Autodesk Fusion 360 part; units mm, degrees
(part 3 of 6)
sketch "OUTLINE - SOFFIT RAIL DOOR FEATURE 15" plane through (0, 0, 2346.24) normal (0, 0, 1) x (1, 0, 0) in component "611205 AIR - SOFFIT TOP RAIL - DOOR SIDE"
  line L0 (579.75, -641.14) -> (586.25, -641.14)
  line L1 (586.25, -641.14) -> (586.25, -635)
  line L2 (586.25, -635) -> (579.75, -635)
  line L3 (579.75, -635) -> (579.75, -641.14)
  dimension "d10633" = 6.5
  dimension "d10634" = 6.14
  dimension "d10635" = 579.75
  dimension "d10636" = 641.14
  constraint horizontal L0
  constraint vertical L1
  constraint horizontal L2
  constraint vertical L3
  measures "d10633" horizontal distance of L0.start L0.end
  measures "d10634" vertical distance of L0.start L2.end
  measures "d10635" horizontal distance of origin L0.start
  measures "d10636" vertical distance of origin L0.start
extrude "CUT - SOFFIT RAIL DOOR FEATURE 15" cut sketch "OUTLINE - SOFFIT RAIL DOOR FEATURE 15" along normal blind 3 bodies 19 in component "611205 AIR - SOFFIT TOP RAIL - DOOR SIDE"
ref_plane "WorkPlane5" through (0, 0, 2346.24) normal (0, 0, 1) x (1, 0, 0) in component "611205 AIR - SOFFIT TOP RAIL - DOOR SIDE"
sketch "HOLE - SOFFIT RAIL DOOR FEATURE 16" plane through (0, 0, 2346.24) normal (0, 0, 1) x (1, 0, 0) in component "611205 AIR - SOFFIT TOP RAIL - DOOR SIDE"
  circle A0 centre (583, -635) radius 3.25
  dimension "d10641" = 6.5
  dimension "d10642" = 583
  dimension "d10643" = 635
  measures "d10641" diameter of A0
  measures "d10642" horizontal distance of origin A0.centre
  measures "d10643" vertical distance of origin A0.centre
extrude "CUT - SOFFIT RAIL DOOR FEATURE 16" cut sketch "HOLE - SOFFIT RAIL DOOR FEATURE 16" along normal blind 3 bodies 19 in component "611205 AIR - SOFFIT TOP RAIL - DOOR SIDE"
ref_plane "WorkPlane4" through (0, 0, 2346.24) normal (0, 0, 1) x (1, 0, 0) in component "611209 AIR - SOFFIT TOP RAIL - ROOM SIDE"
sketch "OUTLINE - SOFFIT RAIL ROOM FEATURE 17" plane through (0, 0, 2346.24) normal (0, 0, 1) x (1, 0, 0) in component "611209 AIR - SOFFIT TOP RAIL - ROOM SIDE"
  line L0 (579.75, -309) -> (586.25, -309)
  line L1 (586.25, -309) -> (586.25, -291)
  line L2 (586.25, -291) -> (579.75, -291)
  line L3 (579.75, -291) -> (579.75, -309)
  dimension "d10648" = 6.5
  dimension "d10649" = 18
  dimension "d10650" = 579.75
  dimension "d10651" = 309
  constraint horizontal L0
  constraint vertical L1
  constraint horizontal L2
  constraint vertical L3
  measures "d10648" horizontal distance of L0.start L0.end
  measures "d10649" vertical distance of L0.start L2.end
  measures "d10650" horizontal distance of origin L0.start
  measures "d10651" vertical distance of origin L0.start
extrude "CUT - SOFFIT RAIL ROOM FEATURE 17" cut sketch "OUTLINE - SOFFIT RAIL ROOM FEATURE 17" along normal blind 3 bodies 20 in component "611209 AIR - SOFFIT TOP RAIL - ROOM SIDE"
ref_plane "WorkPlane5" through (0, 0, 2346.24) normal (0, 0, 1) x (1, 0, 0) in component "611209 AIR - SOFFIT TOP RAIL - ROOM SIDE"
sketch "HOLE - SOFFIT RAIL ROOM FEATURE 18" plane through (0, 0, 2346.24) normal (0, 0, 1) x (1, 0, 0) in component "611209 AIR - SOFFIT TOP RAIL - ROOM SIDE"
  circle A0 centre (583, -291) radius 3.25
  dimension "d10656" = 6.5
  dimension "d10657" = 583
  dimension "d10658" = 291
  measures "d10656" diameter of A0
  measures "d10657" horizontal distance of origin A0.centre
  measures "d10658" vertical distance of origin A0.centre
extrude "CUT - SOFFIT RAIL ROOM FEATURE 18" cut sketch "HOLE - SOFFIT RAIL ROOM FEATURE 18" along normal blind 3 bodies 20 in component "611209 AIR - SOFFIT TOP RAIL - ROOM SIDE"
ref_plane "WorkPlane6" through (0, 0, 2346.24) normal (0, 0, 1) x (1, 0, 0) in component "611209 AIR - SOFFIT TOP RAIL - ROOM SIDE"
sketch "HOLE - SOFFIT RAIL ROOM FEATURE 19" plane through (0, 0, 2346.24) normal (0, 0, 1) x (1, 0, 0) in component "611209 AIR - SOFFIT TOP RAIL - ROOM SIDE"
  circle A0 centre (-1100, -291) radius 3.5
  dimension "d10663" = 7
  dimension "d10664" = 1100
  dimension "d10665" = 291
  measures "d10663" diameter of A0
  measures "d10664" horizontal distance of origin A0.centre
  measures "d10665" vertical distance of origin A0.centre
extrude "CUT - SOFFIT RAIL ROOM FEATURE 19" cut sketch "HOLE - SOFFIT RAIL ROOM FEATURE 19" along normal blind 3 bodies 20 in component "611209 AIR - SOFFIT TOP RAIL - ROOM SIDE"
ref_plane "WorkPlane7" through (0, 0, 2346.24) normal (0, 0, 1) x (1, 0, 0) in component "611209 AIR - SOFFIT TOP RAIL - ROOM SIDE"
sketch "HOLE - SOFFIT RAIL ROOM FEATURE 20" plane through (0, 0, 2346.24) normal (0, 0, 1) x (1, 0, 0) in component "611209 AIR - SOFFIT TOP RAIL - ROOM SIDE"
  circle A0 centre (-950, -291) radius 3.5
  dimension "d10670" = 7
  dimension "d10671" = 950
  dimension "d10672" = 291
  measures "d10670" diameter of A0
  measures "d10671" horizontal distance of origin A0.centre
  measures "d10672" vertical distance of origin A0.centre
extrude "CUT - SOFFIT RAIL ROOM FEATURE 20" cut sketch "HOLE - SOFFIT RAIL ROOM FEATURE 20" along normal blind 3 bodies 20 in component "611209 AIR - SOFFIT TOP RAIL - ROOM SIDE"
ref_plane "WorkPlane4" through (0, -641.14, 0) normal (0, 1, 0) x (0, 0, 1) in component "611210 AIR - SOFFIT DOOR-SIDE PLATE"
sketch "HOLE - SOFFIT DOOR PLATE FEATURE 21" plane through (0, -641.14, 0) normal (0, 1, 0) x (1, 0, 0) in component "611210 AIR - SOFFIT DOOR-SIDE PLATE"
  circle A0 centre (499, -2140.1) radius 7
  dimension "d10677" = 14
  dimension "d10678" = 499
  dimension "d10679" = 2140.1
  measures "d10677" diameter of A0
  measures "d10678" horizontal distance of origin A0.centre
  measures "d10679" vertical distance of origin A0.centre
extrude "CUT - SOFFIT DOOR PLATE FEATURE 21" cut sketch "HOLE - SOFFIT DOOR PLATE FEATURE 21" along normal blind 2 bodies 21 in component "611210 AIR - SOFFIT DOOR-SIDE PLATE"
ref_plane "WorkPlane5" through (0, -641.14, 0) normal (0, 1, 0) x (0, 0, 1) in component "611210 AIR - SOFFIT DOOR-SIDE PLATE"
sketch "HOLE - SOFFIT DOOR PLATE FEATURE 22" plane through (0, -641.14, 0) normal (0, 1, 0) x (1, 0, 0) in component "611210 AIR - SOFFIT DOOR-SIDE PLATE"
  circle A0 centre (821.7, -2140.1) radius 7
  dimension "d10684" = 14
  dimension "d10685" = 821.7
  dimension "d10686" = 2140.1
  measures "d10684" diameter of A0
  measures "d10685" horizontal distance of origin A0.centre
  measures "d10686" vertical distance of origin A0.centre
extrude "CUT - SOFFIT DOOR PLATE FEATURE 22" cut sketch "HOLE - SOFFIT DOOR PLATE FEATURE 22" along normal blind 2 bodies 21 in component "611210 AIR - SOFFIT DOOR-SIDE PLATE"
ref_plane "WorkPlane6" through (0, -641.14, 0) normal (0, 1, 0) x (0, 0, 1) in component "611210 AIR - SOFFIT DOOR-SIDE PLATE"
sketch "HOLE - SOFFIT DOOR PLATE FEATURE 23" plane through (0, -641.14, 0) normal (0, 1, 0) x (1, 0, 0) in component "611210 AIR - SOFFIT DOOR-SIDE PLATE"
  circle A0 centre (1144.4, -2140.1) radius 7
  dimension "d10691" = 14
  dimension "d10692" = 1144.4
  dimension "d10693" = 2140.1
  measures "d10691" diameter of A0
  measures "d10692" horizontal distance of origin A0.centre
  measures "d10693" vertical distance of origin A0.centre
extrude "CUT - SOFFIT DOOR PLATE FEATURE 23" cut sketch "HOLE - SOFFIT DOOR PLATE FEATURE 23" along normal blind 2 bodies 21 in component "611210 AIR - SOFFIT DOOR-SIDE PLATE"
ref_plane "WorkPlane2" through (0, 0, 1698) normal (0, 0, 1) x (1, 0, 0) in component "611404 AIR - FAN BOX BULKHEAD - SUPPLY"
sketch "HOLE - FAN BOX BULKHEAD SUPPLY FEATURE 24" plane through (0, 0, 1698) normal (0, 0, 1) x (1, 0, 0) in component "611404 AIR - FAN BOX BULKHEAD - SUPPLY"
  circle A0 centre (756.5, -741.5) radius 67.5
  dimension "d10698" = 135
  dimension "d10699" = 756.5
  dimension "d10700" = 741.5
  measures "d10698" diameter of A0
  measures "d10699" horizontal distance of origin A0.centre
  measures "d10700" vertical distance of origin A0.centre
extrude "CUT - FAN BOX BULKHEAD SUPPLY FEATURE 24" cut sketch "HOLE - FAN BOX BULKHEAD SUPPLY FEATURE 24" along normal blind 2 bodies 38 in component "611404 AIR - FAN BOX BULKHEAD - SUPPLY"
ref_plane "WorkPlane3" through (0, 0, 1698) normal (0, 0, 1) x (1, 0, 0) in component "611404 AIR - FAN BOX BULKHEAD - SUPPLY"
sketch "HOLE - FAN BOX BULKHEAD SUPPLY FEATURE 25" plane through (0, 0, 1698) normal (0, 0, 1) x (1, 0, 0) in component "611404 AIR - FAN BOX BULKHEAD - SUPPLY"
  circle A0 centre (694.25, -803.75) radius 2.25
  dimension "d10705" = 4.5
  dimension "d10706" = 694.25
  dimension "d10707" = 803.75
  measures "d10705" diameter of A0
  measures "d10706" horizontal distance of origin A0.centre
  measures "d10707" vertical distance of origin A0.centre
extrude "CUT - FAN BOX BULKHEAD SUPPLY FEATURE 25" cut sketch "HOLE - FAN BOX BULKHEAD SUPPLY FEATURE 25" along normal blind 2 bodies 38 in component "611404 AIR - FAN BOX BULKHEAD - SUPPLY"
ref_plane "WorkPlane4" through (0, 0, 1698) normal (0, 0, 1) x (1, 0, 0) in component "611404 AIR - FAN BOX BULKHEAD - SUPPLY"
sketch "HOLE - FAN BOX BULKHEAD SUPPLY FEATURE 26" plane through (0, 0, 1698) normal (0, 0, 1) x (1, 0, 0) in component "611404 AIR - FAN BOX BULKHEAD - SUPPLY"
  circle A0 centre (694.25, -679.25) radius 2.25
  dimension "d10712" = 4.5
  dimension "d10713" = 694.25
  dimension "d10714" = 679.25
  measures "d10712" diameter of A0
  measures "d10713" horizontal distance of origin A0.centre
  measures "d10714" vertical distance of origin A0.centre
extrude "CUT - FAN BOX BULKHEAD SUPPLY FEATURE 26" cut sketch "HOLE - FAN BOX BULKHEAD SUPPLY FEATURE 26" along normal blind 2 bodies 38 in component "611404 AIR - FAN BOX BULKHEAD - SUPPLY"
ref_plane "WorkPlane5" through (0, 0, 1698) normal (0, 0, 1) x (1, 0, 0) in component "611404 AIR - FAN BOX BULKHEAD - SUPPLY"
sketch "HOLE - FAN BOX BULKHEAD SUPPLY FEATURE 27" plane through (0, 0, 1698) normal (0, 0, 1) x (1, 0, 0) in component "611404 AIR - FAN BOX BULKHEAD - SUPPLY"
  circle A0 centre (818.75, -803.75) radius 2.25
  dimension "d10719" = 4.5
  dimension "d10720" = 818.75
  dimension "d10721" = 803.75
  measures "d10719" diameter of A0
  measures "d10720" horizontal distance of origin A0.centre
  measures "d10721" vertical distance of origin A0.centre
extrude "CUT - FAN BOX BULKHEAD SUPPLY FEATURE 27" cut sketch "HOLE - FAN BOX BULKHEAD SUPPLY FEATURE 27" along normal blind 2 bodies 38 in component "611404 AIR - FAN BOX BULKHEAD - SUPPLY"
ref_plane "WorkPlane6" through (0, 0, 1698) normal (0, 0, 1) x (1, 0, 0) in component "611404 AIR - FAN BOX BULKHEAD - SUPPLY"
sketch "HOLE - FAN BOX BULKHEAD SUPPLY FEATURE 28" plane through (0, 0, 1698) normal (0, 0, 1) x (1, 0, 0) in component "611404 AIR - FAN BOX BULKHEAD - SUPPLY"
  circle A0 centre (818.75, -679.25) radius 2.25
  dimension "d10726" = 4.5
  dimension "d10727" = 818.75
  dimension "d10728" = 679.25
  measures "d10726" diameter of A0
  measures "d10727" horizontal distance of origin A0.centre
  measures "d10728" vertical distance of origin A0.centre
extrude "CUT - FAN BOX BULKHEAD SUPPLY FEATURE 28" cut sketch "HOLE - FAN BOX BULKHEAD SUPPLY FEATURE 28" along normal blind 2 bodies 38 in component "611404 AIR - FAN BOX BULKHEAD - SUPPLY"
ref_plane "WorkPlane7" through (0, 0, 1698) normal (0, 0, 1) x (1, 0, 0) in component "611404 AIR - FAN BOX BULKHEAD - SUPPLY"
sketch "HOLE - FAN BOX BULKHEAD SUPPLY FEATURE 29" plane through (0, 0, 1698) normal (0, 0, 1) x (1, 0, 0) in component "611404 AIR - FAN BOX BULKHEAD - SUPPLY"
  circle A0 centre (903.5, -741.5) radius 67.5
  dimension "d10733" = 135
  dimension "d10734" = 903.5
  dimension "d10735" = 741.5
  measures "d10733" diameter of A0
  measures "d10734" horizontal distance of origin A0.centre
  measures "d10735" vertical distance of origin A0.centre
extrude "CUT - FAN BOX BULKHEAD SUPPLY FEATURE 29" cut sketch "HOLE - FAN BOX BULKHEAD SUPPLY FEATURE 29" along normal blind 2 bodies 38 in component "611404 AIR - FAN BOX BULKHEAD - SUPPLY"
ref_plane "WorkPlane8" through (0, 0, 1698) normal (0, 0, 1) x (1, 0, 0) in component "611404 AIR - FAN BOX BULKHEAD - SUPPLY"
sketch "HOLE - FAN BOX BULKHEAD SUPPLY FEATURE 30" plane through (0, 0, 1698) normal (0, 0, 1) x (1, 0, 0) in component "611404 AIR - FAN BOX BULKHEAD - SUPPLY"
  circle A0 centre (841.25, -803.75) radius 2.25
  dimension "d10740" = 4.5
  dimension "d10741" = 841.25
  dimension "d10742" = 803.75
  measures "d10740" diameter of A0
  measures "d10741" horizontal distance of origin A0.centre
  measures "d10742" vertical distance of origin A0.centre
extrude "CUT - FAN BOX BULKHEAD SUPPLY FEATURE 30" cut sketch "HOLE - FAN BOX BULKHEAD SUPPLY FEATURE 30" along normal blind 2 bodies 38 in component "611404 AIR - FAN BOX BULKHEAD - SUPPLY"
ref_plane "WorkPlane9" through (0, 0, 1698) normal (0, 0, 1) x (1, 0, 0) in component "611404 AIR - FAN BOX BULKHEAD - SUPPLY"
sketch "HOLE - FAN BOX BULKHEAD SUPPLY FEATURE 31" plane through (0, 0, 1698) normal (0, 0, 1) x (1, 0, 0) in component "611404 AIR - FAN BOX BULKHEAD - SUPPLY"
  circle A0 centre (841.25, -679.25) radius 2.25
  dimension "d10747" = 4.5
  dimension "d10748" = 841.25
  dimension "d10749" = 679.25
  measures "d10747" diameter of A0
  measures "d10748" horizontal distance of origin A0.centre
  measures "d10749" vertical distance of origin A0.centre
extrude "CUT - FAN BOX BULKHEAD SUPPLY FEATURE 31" cut sketch "HOLE - FAN BOX BULKHEAD SUPPLY FEATURE 31" along normal blind 2 bodies 38 in component "611404 AIR - FAN BOX BULKHEAD - SUPPLY"
ref_plane "WorkPlane10" through (0, 0, 1698) normal (0, 0, 1) x (1, 0, 0) in component "611404 AIR - FAN BOX BULKHEAD - SUPPLY"
sketch "HOLE - FAN BOX BULKHEAD SUPPLY FEATURE 32" plane through (0, 0, 1698) normal (0, 0, 1) x (1, 0, 0) in component "611404 AIR - FAN BOX BULKHEAD - SUPPLY"
  circle A0 centre (965.75, -803.75) radius 2.25
  dimension "d10754" = 4.5
  dimension "d10755" = 965.75
  dimension "d10756" = 803.75
  measures "d10754" diameter of A0
  measures "d10755" horizontal distance of origin A0.centre
  measures "d10756" vertical distance of origin A0.centre
extrude "CUT - FAN BOX BULKHEAD SUPPLY FEATURE 32" cut sketch "HOLE - FAN BOX BULKHEAD SUPPLY FEATURE 32" along normal blind 2 bodies 38 in component "611404 AIR - FAN BOX BULKHEAD - SUPPLY"
ref_plane "WorkPlane11" through (0, 0, 1698) normal (0, 0, 1) x (1, 0, 0) in component "611404 AIR - FAN BOX BULKHEAD - SUPPLY"
sketch "HOLE - FAN BOX BULKHEAD SUPPLY FEATURE 33" plane through (0, 0, 1698) normal (0, 0, 1) x (1, 0, 0) in component "611404 AIR - FAN BOX BULKHEAD - SUPPLY"
  circle A0 centre (965.75, -679.25) radius 2.25
  dimension "d10761" = 4.5
  dimension "d10762" = 965.75
  dimension "d10763" = 679.25
  measures "d10761" diameter of A0
  measures "d10762" horizontal distance of origin A0.centre
  measures "d10763" vertical distance of origin A0.centre
extrude "CUT - FAN BOX BULKHEAD SUPPLY FEATURE 33" cut sketch "HOLE - FAN BOX BULKHEAD SUPPLY FEATURE 33" along normal blind 2 bodies 38 in component "611404 AIR - FAN BOX BULKHEAD - SUPPLY"
ref_plane "WorkPlane2" through (0, 0, 2330) normal (0, 0, 1) x (1, 0, 0) in component "611403 AIR - FAN BOX BULKHEAD - EXHAUST"
sketch "HOLE - FAN BOX BULKHEAD EXHAUST FEATURE 34" plane through (0, 0, 2330) normal (0, 0, 1) x (1, 0, 0) in component "611403 AIR - FAN BOX BULKHEAD - EXHAUST"
  circle A0 centre (939.75, -479.14) radius 67.5
  dimension "d10768" = 135
  dimension "d10769" = 939.75
  dimension "d10770" = 479.14
  measures "d10768" diameter of A0
  measures "d10769" horizontal distance of origin A0.centre
  measures "d10770" vertical distance of origin A0.centre
extrude "CUT - FAN BOX BULKHEAD EXHAUST FEATURE 34" cut sketch "HOLE - FAN BOX BULKHEAD EXHAUST FEATURE 34" along normal blind 2 bodies 33 in component "611403 AIR - FAN BOX BULKHEAD - EXHAUST"
ref_plane "WorkPlane3" through (0, 0, 2330) normal (0, 0, 1) x (1, 0, 0) in component "611403 AIR - FAN BOX BULKHEAD - EXHAUST"
sketch "HOLE - FAN BOX BULKHEAD EXHAUST FEATURE 35" plane through (0, 0, 2330) normal (0, 0, 1) x (1, 0, 0) in component "611403 AIR - FAN BOX BULKHEAD - EXHAUST"
  circle A0 centre (877.5, -541.39) radius 2.25
  dimension "d10775" = 4.5
  dimension "d10776" = 877.5
  dimension "d10777" = 541.39
  measures "d10775" diameter of A0
  measures "d10776" horizontal distance of origin A0.centre
  measures "d10777" vertical distance of origin A0.centre
extrude "CUT - FAN BOX BULKHEAD EXHAUST FEATURE 35" cut sketch "HOLE - FAN BOX BULKHEAD EXHAUST FEATURE 35" along normal blind 2 bodies 33 in component "611403 AIR - FAN BOX BULKHEAD - EXHAUST"
ref_plane "WorkPlane4" through (0, 0, 2330) normal (0, 0, 1) x (1, 0, 0) in component "611403 AIR - FAN BOX BULKHEAD - EXHAUST"
sketch "HOLE - FAN BOX BULKHEAD EXHAUST FEATURE 36" plane through (0, 0, 2330) normal (0, 0, 1) x (1, 0, 0) in component "611403 AIR - FAN BOX BULKHEAD - EXHAUST"
  circle A0 centre (877.5, -416.89) radius 2.25
  dimension "d10782" = 4.5
  dimension "d10783" = 877.5
  dimension "d10784" = 416.89
  measures "d10782" diameter of A0
  measures "d10783" horizontal distance of origin A0.centre
  measures "d10784" vertical distance of origin A0.centre
extrude "CUT - FAN BOX BULKHEAD EXHAUST FEATURE 36" cut sketch "HOLE - FAN BOX BULKHEAD EXHAUST FEATURE 36" along normal blind 2 bodies 33 in component "611403 AIR - FAN BOX BULKHEAD - EXHAUST"
ref_plane "WorkPlane5" through (0, 0, 2330) normal (0, 0, 1) x (1, 0, 0) in component "611403 AIR - FAN BOX BULKHEAD - EXHAUST"
sketch "HOLE - FAN BOX BULKHEAD EXHAUST FEATURE 37" plane through (0, 0, 2330) normal (0, 0, 1) x (1, 0, 0) in component "611403 AIR - FAN BOX BULKHEAD - EXHAUST"
  circle A0 centre (1002, -541.39) radius 2.25
  dimension "d10789" = 4.5
  dimension "d10790" = 1002
  dimension "d10791" = 541.39
  measures "d10789" diameter of A0
  measures "d10790" horizontal distance of origin A0.centre
  measures "d10791" vertical distance of origin A0.centre
extrude "CUT - FAN BOX BULKHEAD EXHAUST FEATURE 37" cut sketch "HOLE - FAN BOX BULKHEAD EXHAUST FEATURE 37" along normal blind 2 bodies 33 in component "611403 AIR - FAN BOX BULKHEAD - EXHAUST"
ref_plane "WorkPlane6" through (0, 0, 2330) normal (0, 0, 1) x (1, 0, 0) in component "611403 AIR - FAN BOX BULKHEAD - EXHAUST"
sketch "HOLE - FAN BOX BULKHEAD EXHAUST FEATURE 38" plane through (0, 0, 2330) normal (0, 0, 1) x (1, 0, 0) in component "611403 AIR - FAN BOX BULKHEAD - EXHAUST"
  circle A0 centre (1002, -416.89) radius 2.25
  dimension "d10796" = 4.5
  dimension "d10797" = 1002
  dimension "d10798" = 416.89
  measures "d10796" diameter of A0
  measures "d10797" horizontal distance of origin A0.centre
  measures "d10798" vertical distance of origin A0.centre
extrude "CUT - FAN BOX BULKHEAD EXHAUST FEATURE 38" cut sketch "HOLE - FAN BOX BULKHEAD EXHAUST FEATURE 38" along normal blind 2 bodies 33 in component "611403 AIR - FAN BOX BULKHEAD - EXHAUST"
ref_plane "WorkPlane7" through (0, 0, 2330) normal (0, 0, 1) x (1, 0, 0) in component "611403 AIR - FAN BOX BULKHEAD - EXHAUST"
sketch "HOLE - FAN BOX BULKHEAD EXHAUST FEATURE 39" plane through (0, 0, 2330) normal (0, 0, 1) x (1, 0, 0) in component "611403 AIR - FAN BOX BULKHEAD - EXHAUST"
  circle A0 centre (1085.25, -479.14) radius 67.5
  dimension "d10803" = 135
  dimension "d10804" = 1085.25
  dimension "d10805" = 479.14
  measures "d10803" diameter of A0
  measures "d10804" horizontal distance of origin A0.centre
  measures "d10805" vertical distance of origin A0.centre
extrude "CUT - FAN BOX BULKHEAD EXHAUST FEATURE 39" cut sketch "HOLE - FAN BOX BULKHEAD EXHAUST FEATURE 39" along normal blind 2 bodies 33 in component "611403 AIR - FAN BOX BULKHEAD - EXHAUST"
ref_plane "WorkPlane8" through (0, 0, 2330) normal (0, 0, 1) x (1, 0, 0) in component "611403 AIR - FAN BOX BULKHEAD - EXHAUST"
sketch "HOLE - FAN BOX BULKHEAD EXHAUST FEATURE 40" plane through (0, 0, 2330) normal (0, 0, 1) x (1, 0, 0) in component "611403 AIR - FAN BOX BULKHEAD - EXHAUST"
  circle A0 centre (1023, -541.39) radius 2.25
  dimension "d10810" = 4.5
  dimension "d10811" = 1023
  dimension "d10812" = 541.39
  measures "d10810" diameter of A0
  measures "d10811" horizontal distance of origin A0.centre
  measures "d10812" vertical distance of origin A0.centre
extrude "CUT - FAN BOX BULKHEAD EXHAUST FEATURE 40" cut sketch "HOLE - FAN BOX BULKHEAD EXHAUST FEATURE 40" along normal blind 2 bodies 33 in component "611403 AIR - FAN BOX BULKHEAD - EXHAUST"
ref_plane "WorkPlane9" through (0, 0, 2330) normal (0, 0, 1) x (1, 0, 0) in component "611403 AIR - FAN BOX BULKHEAD - EXHAUST"
sketch "HOLE - FAN BOX BULKHEAD EXHAUST FEATURE 41" plane through (0, 0, 2330) normal (0, 0, 1) x (1, 0, 0) in component "611403 AIR - FAN BOX BULKHEAD - EXHAUST"
  circle A0 centre (1023, -416.89) radius 2.25
  dimension "d10817" = 4.5
  dimension "d10818" = 1023
  dimension "d10819" = 416.89
  measures "d10817" diameter of A0
  measures "d10818" horizontal distance of origin A0.centre
  measures "d10819" vertical distance of origin A0.centre
extrude "CUT - FAN BOX BULKHEAD EXHAUST FEATURE 41" cut sketch "HOLE - FAN BOX BULKHEAD EXHAUST FEATURE 41" along normal blind 2 bodies 33 in component "611403 AIR - FAN BOX BULKHEAD - EXHAUST"
ref_plane "WorkPlane10" through (0, 0, 2330) normal (0, 0, 1) x (1, 0, 0) in component "611403 AIR - FAN BOX BULKHEAD - EXHAUST"
sketch "HOLE - FAN BOX BULKHEAD EXHAUST FEATURE 42" plane through (0, 0, 2330) normal (0, 0, 1) x (1, 0, 0) in component "611403 AIR - FAN BOX BULKHEAD - EXHAUST"
  circle A0 centre (1147.5, -541.39) radius 2.25
  dimension "d10824" = 4.5
  dimension "d10825" = 1147.5
  dimension "d10826" = 541.39
  measures "d10824" diameter of A0
  measures "d10825" horizontal distance of origin A0.centre
  measures "d10826" vertical distance of origin A0.centre
extrude "CUT - FAN BOX BULKHEAD EXHAUST FEATURE 42" cut sketch "HOLE - FAN BOX BULKHEAD EXHAUST FEATURE 42" along normal blind 2 bodies 33 in component "611403 AIR - FAN BOX BULKHEAD - EXHAUST"
ref_plane "WorkPlane11" through (0, 0, 2330) normal (0, 0, 1) x (1, 0, 0) in component "611403 AIR - FAN BOX BULKHEAD - EXHAUST"
sketch "HOLE - FAN BOX BULKHEAD EXHAUST FEATURE 43" plane through (0, 0, 2330) normal (0, 0, 1) x (1, 0, 0) in component "611403 AIR - FAN BOX BULKHEAD - EXHAUST"
  circle A0 centre (1147.5, -416.89) radius 2.25
  dimension "d10831" = 4.5
  dimension "d10832" = 1147.5
  dimension "d10833" = 416.89
  measures "d10831" diameter of A0
  measures "d10832" horizontal distance of origin A0.centre
  measures "d10833" vertical distance of origin A0.centre
extrude "CUT - FAN BOX BULKHEAD EXHAUST FEATURE 43" cut sketch "HOLE - FAN BOX BULKHEAD EXHAUST FEATURE 43" along normal blind 2 bodies 33 in component "611403 AIR - FAN BOX BULKHEAD - EXHAUST"
ref_plane "WorkPlane2" through (0, -803, 0) normal (0, 1, 0) x (0, 0, 1) in component "611501 AIR - INTAKE RISER"
sketch "HOLE - INTAKE RISER FEATURE 44" plane through (0, -803, 0) normal (0, 1, 0) x (1, 0, 0) in component "611501 AIR - INTAKE RISER"
  circle A0 centre (994.35, -844) radius 5
  dimension "d10838" = 10
  dimension "d10839" = 994.35
  dimension "d10840" = 844
  measures "d10838" diameter of A0
  measures "d10839" horizontal distance of origin A0.centre
  measures "d10840" vertical distance of origin A0.centre
extrude "CUT - INTAKE RISER FEATURE 44" cut sketch "HOLE - INTAKE RISER FEATURE 44" along normal blind 1 bodies 44 in component "611501 AIR - INTAKE RISER"
ref_plane "WorkPlane4" through (0, 0, 2400) normal (0, 0, 1) x (1, 0, 0) in component "611601 AIR - ROOF SLEEVE"
sketch "HOLE - ROOF SLEEVE FEATURE 45" plane through (0, 0, 2400) normal (0, 0, 1) x (1, 0, 0) in component "611601 AIR - ROOF SLEEVE"
  circle A0 centre (852, -600) radius 5
  dimension "d10845" = 10
  dimension "d10846" = 852
  dimension "d10847" = 600
  measures "d10845" diameter of A0
  measures "d10846" horizontal distance of origin A0.centre
  measures "d10847" vertical distance of origin A0.centre
extrude "CUT - ROOF SLEEVE FEATURE 45" cut sketch "HOLE - ROOF SLEEVE FEATURE 45" along normal blind 1 bodies 46 in component "611601 AIR - ROOF SLEEVE"
ref_plane "WorkPlane2" through (0, 0, 2401) normal (0, 0, 1) x (1, 0, 0) in component "611602 AIR - ROOF GRILLE"
sketch "HOLE - ROOF GRILLE FEATURE 46" plane through (0, 0, 2401) normal (0, 0, 1) x (1, 0, 0) in component "611602 AIR - ROOF GRILLE"
  circle A0 centre (852, -600) radius 3.5
  dimension "d10852" = 7
  dimension "d10853" = 852
  dimension "d10854" = 600
  measures "d10852" diameter of A0
  measures "d10853" horizontal distance of origin A0.centre
  measures "d10854" vertical distance of origin A0.centre
extrude "CUT - ROOF GRILLE FEATURE 46" cut sketch "HOLE - ROOF GRILLE FEATURE 46" along normal blind 2 bodies 47 in component "611602 AIR - ROOF GRILLE"
ref_plane "WorkPlane5" through (0, 0, 2400) normal (0, 0, 1) x (1, 0, 0) in component "611601 AIR - ROOF SLEEVE"
sketch "HOLE - ROOF SLEEVE FEATURE 47" plane through (0, 0, 2400) normal (0, 0, 1) x (1, 0, 0) in component "611601 AIR - ROOF SLEEVE"
  circle A0 centre (852, -346) radius 5
  dimension "d10859" = 10
  dimension "d10860" = 852
  dimension "d10861" = 346
  measures "d10859" diameter of A0
  measures "d10860" horizontal distance of origin A0.centre
  measures "d10861" vertical distance of origin A0.centre
extrude "CUT - ROOF SLEEVE FEATURE 47" cut sketch "HOLE - ROOF SLEEVE FEATURE 47" along normal blind 1 bodies 46 in component "611601 AIR - ROOF SLEEVE"
ref_plane "WorkPlane3" through (0, 0, 2401) normal (0, 0, 1) x (1, 0, 0) in component "611602 AIR - ROOF GRILLE"
sketch "HOLE - ROOF GRILLE FEATURE 48" plane through (0, 0, 2401) normal (0, 0, 1) x (1, 0, 0) in component "611602 AIR - ROOF GRILLE"
  circle A0 centre (852, -346) radius 3.5
  dimension "d10866" = 7
  dimension "d10867" = 852
  dimension "d10868" = 346
  measures "d10866" diameter of A0
  measures "d10867" horizontal distance of origin A0.centre
  measures "d10868" vertical distance of origin A0.centre
extrude "CUT - ROOF GRILLE FEATURE 48" cut sketch "HOLE - ROOF GRILLE FEATURE 48" along normal blind 2 bodies 47 in component "611602 AIR - ROOF GRILLE"
ref_plane "WorkPlane6" through (0, 0, 2400) normal (0, 0, 1) x (1, 0, 0) in component "611601 AIR - ROOF SLEEVE"
sketch "HOLE - ROOF SLEEVE FEATURE 49" plane through (0, 0, 2400) normal (0, 0, 1) x (1, 0, 0) in component "611601 AIR - ROOF SLEEVE"
  circle A0 centre (892, -273) radius 5
  dimension "d10873" = 10
  dimension "d10874" = 892
  dimension "d10875" = 273
  measures "d10873" diameter of A0
  measures "d10874" horizontal distance of origin A0.centre
  measures "d10875" vertical distance of origin A0.centre
extrude "CUT - ROOF SLEEVE FEATURE 49" cut sketch "HOLE - ROOF SLEEVE FEATURE 49" along normal blind 1 bodies 46 in component "611601 AIR - ROOF SLEEVE"
ref_plane "WorkPlane4" through (0, 0, 2401) normal (0, 0, 1) x (1, 0, 0) in component "611602 AIR - ROOF GRILLE"
sketch "HOLE - ROOF GRILLE FEATURE 50" plane through (0, 0, 2401) normal (0, 0, 1) x (1, 0, 0) in component "611602 AIR - ROOF GRILLE"
  circle A0 centre (892, -273) radius 3.5
  dimension "d10880" = 7
  dimension "d10881" = 892
  dimension "d10882" = 273
  measures "d10880" diameter of A0
  measures "d10881" horizontal distance of origin A0.centre
  measures "d10882" vertical distance of origin A0.centre
extrude "CUT - ROOF GRILLE FEATURE 50" cut sketch "HOLE - ROOF GRILLE FEATURE 50" along normal blind 2 bodies 47 in component "611602 AIR - ROOF GRILLE"
ref_plane "WorkPlane7" through (0, 0, 2400) normal (0, 0, 1) x (1, 0, 0) in component "611601 AIR - ROOF SLEEVE"
sketch "HOLE - ROOF SLEEVE FEATURE 51" plane through (0, 0, 2400) normal (0, 0, 1) x (1, 0, 0) in component "611601 AIR - ROOF SLEEVE"
  circle A0 centre (1137, -273) radius 5
  dimension "d10887" = 10
  dimension "d10888" = 1137
  dimension "d10889" = 273
  measures "d10887" diameter of A0
  measures "d10888" horizontal distance of origin A0.centre
  measures "d10889" vertical distance of origin A0.centre
extrude "CUT - ROOF SLEEVE FEATURE 51" cut sketch "HOLE - ROOF SLEEVE FEATURE 51" along normal blind 1 bodies 46 in component "611601 AIR - ROOF SLEEVE"
ref_plane "WorkPlane5" through (0, 0, 2401) normal (0, 0, 1) x (1, 0, 0) in component "611602 AIR - ROOF GRILLE"
sketch "HOLE - ROOF GRILLE FEATURE 52" plane through (0, 0, 2401) normal (0, 0, 1) x (1, 0, 0) in component "611602 AIR - ROOF GRILLE"
  circle A0 centre (1137, -273) radius 3.5
  dimension "d10894" = 7
  dimension "d10895" = 1137
  dimension "d10896" = 273
  measures "d10894" diameter of A0
  measures "d10895" horizontal distance of origin A0.centre
  measures "d10896" vertical distance of origin A0.centre
extrude "CUT - ROOF GRILLE FEATURE 52" cut sketch "HOLE - ROOF GRILLE FEATURE 52" along normal blind 2 bodies 47 in component "611602 AIR - ROOF GRILLE"
ref_plane "WorkPlane3" through (959, 0, 0) normal (1, 0, 0) x (0, 1, 0) in component "611501 AIR - INTAKE RISER"
sketch "HOLE - INTAKE RISER FEATURE 53" plane through (959, 0, 0) normal (1, 0, 0) x (0, 0, -1) in component "611501 AIR - INTAKE RISER"
  circle A0 centre (-1373.5, -778.5) radius 2.05
  dimension "d10901" = 4.1
  dimension "d10902" = 778.5
  dimension "d10903" = 1373.5
  measures "d10901" diameter of A0
  measures "d10902" vertical distance of origin A0.centre
  measures "d10903" horizontal distance of origin A0.centre
extrude "CUT - INTAKE RISER FEATURE 53" cut sketch "HOLE - INTAKE RISER FEATURE 53" along normal blind 1 bodies 44 in component "611501 AIR - INTAKE RISER"
ref_plane "WorkPlane4" through (1097, 0, 0) normal (1, 0, 0) x (0, 1, 0) in component "611501 AIR - INTAKE RISER"
sketch "HOLE - INTAKE RISER FEATURE 54" plane through (1097, 0, 0) normal (1, 0, 0) x (0, 0, -1) in component "611501 AIR - INTAKE RISER"
  circle A0 centre (-1373.5, -778.5) radius 2.05
  dimension "d10908" = 4.1
  dimension "d10909" = 778.5
  dimension "d10910" = 1373.5
  measures "d10908" diameter of A0
  measures "d10909" vertical distance of origin A0.centre
  measures "d10910" horizontal distance of origin A0.centre
extrude "CUT - INTAKE RISER FEATURE 54" cut sketch "HOLE - INTAKE RISER FEATURE 54" along normal blind 1 bodies 44 in component "611501 AIR - INTAKE RISER"
ref_plane "WorkPlane5" through (959, 0, 0) normal (1, 0, 0) x (0, 1, 0) in component "611501 AIR - INTAKE RISER"
sketch "HOLE - INTAKE RISER FEATURE 55" plane through (959, 0, 0) normal (1, 0, 0) x (0, 0, -1) in component "611501 AIR - INTAKE RISER"
  circle A0 centre (-1373.5, -728) radius 2.05
  dimension "d10915" = 4.1
  dimension "d10916" = 728
  dimension "d10917" = 1373.5
  measures "d10915" diameter of A0
  measures "d10916" vertical distance of origin A0.centre
  measures "d10917" horizontal distance of origin A0.centre
extrude "CUT - INTAKE RISER FEATURE 55" cut sketch "HOLE - INTAKE RISER FEATURE 55" along normal blind 1 bodies 44 in component "611501 AIR - INTAKE RISER"
ref_plane "WorkPlane6" through (1097, 0, 0) normal (1, 0, 0) x (0, 1, 0) in component "611501 AIR - INTAKE RISER"
sketch "HOLE - INTAKE RISER FEATURE 56" plane through (1097, 0, 0) normal (1, 0, 0) x (0, 0, -1) in component "611501 AIR - INTAKE RISER"
  circle A0 centre (-1373.5, -728) radius 2.05
  dimension "d10922" = 4.1
  dimension "d10923" = 728
  dimension "d10924" = 1373.5
  measures "d10922" diameter of A0
  measures "d10923" vertical distance of origin A0.centre
  measures "d10924" horizontal distance of origin A0.centre
extrude "CUT - INTAKE RISER FEATURE 56" cut sketch "HOLE - INTAKE RISER FEATURE 56" along normal blind 1 bodies 44 in component "611501 AIR - INTAKE RISER"
ref_plane "WorkPlane7" through (959, 0, 0) normal (1, 0, 0) x (0, 1, 0) in component "611501 AIR - INTAKE RISER"
sketch "HOLE - INTAKE RISER FEATURE 57" plane through (959, 0, 0) normal (1, 0, 0) x (0, 0, -1) in component "611501 AIR - INTAKE RISER"
  circle A0 centre (-1373.5, -677.5) radius 2.05
  dimension "d10929" = 4.1
  dimension "d10930" = 677.5
  dimension "d10931" = 1373.5
  measures "d10929" diameter of A0
  measures "d10930" vertical distance of origin A0.centre
  measures "d10931" horizontal distance of origin A0.centre
extrude "CUT - INTAKE RISER FEATURE 57" cut sketch "HOLE - INTAKE RISER FEATURE 57" along normal blind 1 bodies 44 in component "611501 AIR - INTAKE RISER"
ref_plane "WorkPlane8" through (1097, 0, 0) normal (1, 0, 0) x (0, 1, 0) in component "611501 AIR - INTAKE RISER"
sketch "HOLE - INTAKE RISER FEATURE 58" plane through (1097, 0, 0) normal (1, 0, 0) x (0, 0, -1) in component "611501 AIR - INTAKE RISER"
  circle A0 centre (-1373.5, -677.5) radius 2.05
  dimension "d10936" = 4.1
  dimension "d10937" = 677.5
  dimension "d10938" = 1373.5
  measures "d10936" diameter of A0
  measures "d10937" vertical distance of origin A0.centre
  measures "d10938" horizontal distance of origin A0.centre
extrude "CUT - INTAKE RISER FEATURE 58" cut sketch "HOLE - INTAKE RISER FEATURE 58" along normal blind 1 bodies 44 in component "611501 AIR - INTAKE RISER"
ref_plane "WorkPlane9" through (0, -803, 0) normal (0, 1, 0) x (0, 0, 1) in component "611501 AIR - INTAKE RISER"
sketch "HOLE - INTAKE RISER FEATURE 59" plane through (0, -803, 0) normal (0, 1, 0) x (1, 0, 0) in component "611501 AIR - INTAKE RISER"
  circle A0 centre (992.5, -1373.5) radius 2.05
  dimension "d10943" = 4.1
  dimension "d10944" = 992.5
  dimension "d10945" = 1373.5
  measures "d10943" diameter of A0
  measures "d10944" horizontal distance of origin A0.centre
  measures "d10945" vertical distance of origin A0.centre
extrude "CUT - INTAKE RISER FEATURE 59" cut sketch "HOLE - INTAKE RISER FEATURE 59" along normal blind 1 bodies 44 in component "611501 AIR - INTAKE RISER"
ref_plane "WorkPlane10" through (0, -654, 0) normal (0, 1, 0) x (0, 0, 1) in component "611501 AIR - INTAKE RISER"
sketch "HOLE - INTAKE RISER FEATURE 60" plane through (0, -654, 0) normal (0, 1, 0) x (1, 0, 0) in component "611501 AIR - INTAKE RISER"
  circle A0 centre (992.5, -1373.5) radius 2.05
  dimension "d10950" = 4.1
  dimension "d10951" = 992.5
  dimension "d10952" = 1373.5
  measures "d10950" diameter of A0
  measures "d10951" horizontal distance of origin A0.centre
  measures "d10952" vertical distance of origin A0.centre
extrude "CUT - INTAKE RISER FEATURE 60" cut sketch "HOLE - INTAKE RISER FEATURE 60" along normal blind 1 bodies 44 in component "611501 AIR - INTAKE RISER"
ref_plane "WorkPlane11" through (0, -803, 0) normal (0, 1, 0) x (0, 0, 1) in component "611501 AIR - INTAKE RISER"
sketch "HOLE - INTAKE RISER FEATURE 61" plane through (0, -803, 0) normal (0, 1, 0) x (1, 0, 0) in component "611501 AIR - INTAKE RISER"
  circle A0 centre (1051.5, -1373.5) radius 2.05
  dimension "d10957" = 4.1
  dimension "d10958" = 1051.5
  dimension "d10959" = 1373.5
  measures "d10957" diameter of A0
  measures "d10958" horizontal distance of origin A0.centre
  measures "d10959" vertical distance of origin A0.centre
extrude "CUT - INTAKE RISER FEATURE 61" cut sketch "HOLE - INTAKE RISER FEATURE 61" along normal blind 1 bodies 44 in component "611501 AIR - INTAKE RISER"
ref_plane "WorkPlane12" through (0, -654, 0) normal (0, 1, 0) x (0, 0, 1) in component "611501 AIR - INTAKE RISER"
sketch "HOLE - INTAKE RISER FEATURE 62" plane through (0, -654, 0) normal (0, 1, 0) x (1, 0, 0) in component "611501 AIR - INTAKE RISER"
  circle A0 centre (1051.5, -1373.5) radius 2.05
  dimension "d10964" = 4.1
  dimension "d10965" = 1051.5
  dimension "d10966" = 1373.5
  measures "d10964" diameter of A0
  measures "d10965" horizontal distance of origin A0.centre
  measures "d10966" vertical distance of origin A0.centre
extrude "CUT - INTAKE RISER FEATURE 62" cut sketch "HOLE - INTAKE RISER FEATURE 62" along normal blind 1 bodies 44 in component "611501 AIR - INTAKE RISER"
ref_plane "WorkPlane2" through (680, 0, 0) normal (1, 0, 0) x (0, 1, 0) in component "611402 AIR - FAN BOX CASING - SUPPLY"
sketch "HOLE - SUPPLY FAN BOX FEATURE 63" plane through (680, 0, 0) normal (1, 0, 0) x (0, 0, -1) in component "611402 AIR - FAN BOX CASING - SUPPLY"
  circle A0 centre (-1660, -792) radius 2.05
  dimension "d10971" = 4.1
  dimension "d10972" = 792
  dimension "d10973" = 1660
  measures "d10971" diameter of A0
  measures "d10972" vertical distance of origin A0.centre
  measures "d10973" horizontal distance of origin A0.centre
extrude "CUT - SUPPLY FAN BOX FEATURE 63" cut sketch "HOLE - SUPPLY FAN BOX FEATURE 63" along normal blind 3 bodies 37 in component "611402 AIR - FAN BOX CASING - SUPPLY"
ref_plane "WorkPlane3" through (977, 0, 0) normal (1, 0, 0) x (0, 1, 0) in component "611402 AIR - FAN BOX CASING - SUPPLY"
sketch "HOLE - SUPPLY FAN BOX FEATURE 64" plane through (977, 0, 0) normal (1, 0, 0) x (0, 0, -1) in component "611402 AIR - FAN BOX CASING - SUPPLY"
  circle A0 centre (-1660, -792) radius 2.05
  dimension "d10978" = 4.1
  dimension "d10979" = 792
  dimension "d10980" = 1660
  measures "d10978" diameter of A0
  measures "d10979" vertical distance of origin A0.centre
  measures "d10980" horizontal distance of origin A0.centre
extrude "CUT - SUPPLY FAN BOX FEATURE 64" cut sketch "HOLE - SUPPLY FAN BOX FEATURE 64" along normal blind 3 bodies 37 in component "611402 AIR - FAN BOX CASING - SUPPLY"
ref_plane "WorkPlane4" through (680, 0, 0) normal (1, 0, 0) x (0, 1, 0) in component "611402 AIR - FAN BOX CASING - SUPPLY"
sketch "HOLE - SUPPLY FAN BOX FEATURE 65" plane through (680, 0, 0) normal (1, 0, 0) x (0, 0, -1) in component "611402 AIR - FAN BOX CASING - SUPPLY"
  circle A0 centre (-1660, -741.5) radius 2.05
  dimension "d10985" = 4.1
  dimension "d10986" = 741.5
  dimension "d10987" = 1660
  measures "d10985" diameter of A0
  measures "d10986" vertical distance of origin A0.centre
  measures "d10987" horizontal distance of origin A0.centre
extrude "CUT - SUPPLY FAN BOX FEATURE 65" cut sketch "HOLE - SUPPLY FAN BOX FEATURE 65" along normal blind 3 bodies 37 in component "611402 AIR - FAN BOX CASING - SUPPLY"
ref_plane "WorkPlane5" through (977, 0, 0) normal (1, 0, 0) x (0, 1, 0) in component "611402 AIR - FAN BOX CASING - SUPPLY"
sketch "HOLE - SUPPLY FAN BOX FEATURE 66" plane through (977, 0, 0) normal (1, 0, 0) x (0, 0, -1) in component "611402 AIR - FAN BOX CASING - SUPPLY"
  circle A0 centre (-1660, -741.5) radius 2.05
  dimension "d10992" = 4.1
  dimension "d10993" = 741.5
  dimension "d10994" = 1660
  measures "d10992" diameter of A0
  measures "d10993" vertical distance of origin A0.centre
  measures "d10994" horizontal distance of origin A0.centre
extrude "CUT - SUPPLY FAN BOX FEATURE 66" cut sketch "HOLE - SUPPLY FAN BOX FEATURE 66" along normal blind 3 bodies 37 in component "611402 AIR - FAN BOX CASING - SUPPLY"
ref_plane "WorkPlane6" through (680, 0, 0) normal (1, 0, 0) x (0, 1, 0) in component "611402 AIR - FAN BOX CASING - SUPPLY"
sketch "HOLE - SUPPLY FAN BOX FEATURE 67" plane through (680, 0, 0) normal (1, 0, 0) x (0, 0, -1) in component "611402 AIR - FAN BOX CASING - SUPPLY"
  circle A0 centre (-1660, -691) radius 2.05
  dimension "d10999" = 4.1
  dimension "d11000" = 691
  dimension "d11001" = 1660
  measures "d10999" diameter of A0
  measures "d11000" vertical distance of origin A0.centre
  measures "d11001" horizontal distance of origin A0.centre
extrude "CUT - SUPPLY FAN BOX FEATURE 67" cut sketch "HOLE - SUPPLY FAN BOX FEATURE 67" along normal blind 3 bodies 37 in component "611402 AIR - FAN BOX CASING - SUPPLY"
ref_plane "WorkPlane7" through (977, 0, 0) normal (1, 0, 0) x (0, 1, 0) in component "611402 AIR - FAN BOX CASING - SUPPLY"
sketch "HOLE - SUPPLY FAN BOX FEATURE 68" plane through (977, 0, 0) normal (1, 0, 0) x (0, 0, -1) in component "611402 AIR - FAN BOX CASING - SUPPLY"
  circle A0 centre (-1660, -691) radius 2.05
  dimension "d11006" = 4.1
  dimension "d11007" = 691
  dimension "d11008" = 1660
  measures "d11006" diameter of A0
  measures "d11007" vertical distance of origin A0.centre
  measures "d11008" horizontal distance of origin A0.centre
extrude "CUT - SUPPLY FAN BOX FEATURE 68" cut sketch "HOLE - SUPPLY FAN BOX FEATURE 68" along normal blind 3 bodies 37 in component "611402 AIR - FAN BOX CASING - SUPPLY"
ref_plane "WorkPlane8" through (0, -819, 0) normal (0, 1, 0) x (0, 0, 1) in component "611402 AIR - FAN BOX CASING - SUPPLY"
sketch "HOLE - SUPPLY FAN BOX FEATURE 69" plane through (0, -819, 0) normal (0, 1, 0) x (1, 0, 0) in component "611402 AIR - FAN BOX CASING - SUPPLY"
  circle A0 centre (748, -1941) radius 2.05
  dimension "d11013" = 4.1
  dimension "d11014" = 748
  dimension "d11015" = 1941
  measures "d11013" diameter of A0
  measures "d11014" horizontal distance of origin A0.centre
  measures "d11015" vertical distance of origin A0.centre
extrude "CUT - SUPPLY FAN BOX FEATURE 69" cut sketch "HOLE - SUPPLY FAN BOX FEATURE 69" along normal blind 3 bodies 37 in component "611402 AIR - FAN BOX CASING - SUPPLY"
ref_plane "WorkPlane9" through (0, -819, 0) normal (0, 1, 0) x (0, 0, 1) in component "611402 AIR - FAN BOX CASING - SUPPLY"
sketch "HOLE - SUPPLY FAN BOX FEATURE 70" plane through (0, -819, 0) normal (0, 1, 0) x (1, 0, 0) in component "611402 AIR - FAN BOX CASING - SUPPLY"
  circle A0 centre (802.6667, -1941) radius 2.05
  dimension "d11020" = 4.1
  dimension "d11021" = 802.6667
  dimension "d11022" = 1941
  measures "d11020" diameter of A0
  measures "d11021" horizontal distance of origin A0.centre
  measures "d11022" vertical distance of origin A0.centre
extrude "CUT - SUPPLY FAN BOX FEATURE 70" cut sketch "HOLE - SUPPLY FAN BOX FEATURE 70" along normal blind 3 bodies 37 in component "611402 AIR - FAN BOX CASING - SUPPLY"
ref_plane "WorkPlane10" through (0, -819, 0) normal (0, 1, 0) x (0, 0, 1) in component "611402 AIR - FAN BOX CASING - SUPPLY"
sketch "HOLE - SUPPLY FAN BOX FEATURE 71" plane through (0, -819, 0) normal (0, 1, 0) x (1, 0, 0) in component "611402 AIR - FAN BOX CASING - SUPPLY"
  circle A0 centre (857.3333, -1941) radius 2.05
  dimension "d11027" = 4.1
  dimension "d11028" = 857.3333
  dimension "d11029" = 1941
  measures "d11027" diameter of A0
  measures "d11028" horizontal distance of origin A0.centre
  measures "d11029" vertical distance of origin A0.centre
extrude "CUT - SUPPLY FAN BOX FEATURE 71" cut sketch "HOLE - SUPPLY FAN BOX FEATURE 71" along normal blind 3 bodies 37 in component "611402 AIR - FAN BOX CASING - SUPPLY"
ref_plane "WorkPlane11" through (0, -819, 0) normal (0, 1, 0) x (0, 0, 1) in component "611402 AIR - FAN BOX CASING - SUPPLY"
sketch "HOLE - SUPPLY FAN BOX FEATURE 72" plane through (0, -819, 0) normal (0, 1, 0) x (1, 0, 0) in component "611402 AIR - FAN BOX CASING - SUPPLY"
  circle A0 centre (912, -1941) radius 2.05
  dimension "d11034" = 4.1
  dimension "d11035" = 912
  dimension "d11036" = 1941
  measures "d11034" diameter of A0
  measures "d11035" horizontal distance of origin A0.centre
  measures "d11036" vertical distance of origin A0.centre
extrude "CUT - SUPPLY FAN BOX FEATURE 72" cut sketch "HOLE - SUPPLY FAN BOX FEATURE 72" along normal blind 3 bodies 37 in component "611402 AIR - FAN BOX CASING - SUPPLY"
ref_plane "WorkPlane12" through (0, -667, 0) normal (0, 1, 0) x (0, 0, 1) in component "611402 AIR - FAN BOX CASING - SUPPLY"
sketch "HOLE - SUPPLY FAN BOX FEATURE 73" plane through (0, -667, 0) normal (0, 1, 0) x (1, 0, 0) in component "611402 AIR - FAN BOX CASING - SUPPLY"
  circle A0 centre (750.9, -1891.5) radius 2.05
  dimension "d11041" = 4.1
  dimension "d11042" = 750.9
  dimension "d11043" = 1891.5
  measures "d11041" diameter of A0
  measures "d11042" horizontal distance of origin A0.centre
  measures "d11043" vertical distance of origin A0.centre
extrude "CUT - SUPPLY FAN BOX FEATURE 73" cut sketch "HOLE - SUPPLY FAN BOX FEATURE 73" along normal blind 3 bodies 37 in component "611402 AIR - FAN BOX CASING - SUPPLY"
ref_plane "WorkPlane13" through (0, -667, 0) normal (0, 1, 0) x (0, 0, 1) in component "611402 AIR - FAN BOX CASING - SUPPLY"
sketch "HOLE - SUPPLY FAN BOX FEATURE 74" plane through (0, -667, 0) normal (0, 1, 0) x (1, 0, 0) in component "611402 AIR - FAN BOX CASING - SUPPLY"
  circle A0 centre (805.3, -1891.5) radius 2.05
  dimension "d11048" = 4.1
  dimension "d11049" = 805.3
  dimension "d11050" = 1891.5
  measures "d11048" diameter of A0
  measures "d11049" horizontal distance of origin A0.centre
  measures "d11050" vertical distance of origin A0.centre
extrude "CUT - SUPPLY FAN BOX FEATURE 74" cut sketch "HOLE - SUPPLY FAN BOX FEATURE 74" along normal blind 3 bodies 37 in component "611402 AIR - FAN BOX CASING - SUPPLY"
ref_plane "WorkPlane14" through (0, -667, 0) normal (0, 1, 0) x (0, 0, 1) in component "611402 AIR - FAN BOX CASING - SUPPLY"
sketch "HOLE - SUPPLY FAN BOX FEATURE 75" plane through (0, -667, 0) normal (0, 1, 0) x (1, 0, 0) in component "611402 AIR - FAN BOX CASING - SUPPLY"
  circle A0 centre (859.7, -1891.5) radius 2.05
  dimension "d11055" = 4.1
  dimension "d11056" = 859.7
  dimension "d11057" = 1891.5
  measures "d11055" diameter of A0
  measures "d11056" horizontal distance of origin A0.centre
  measures "d11057" vertical distance of origin A0.centre
extrude "CUT - SUPPLY FAN BOX FEATURE 75" cut sketch "HOLE - SUPPLY FAN BOX FEATURE 75" along normal blind 3 bodies 37 in component "611402 AIR - FAN BOX CASING - SUPPLY"
ref_plane "WorkPlane15" through (0, -667, 0) normal (0, 1, 0) x (0, 0, 1) in component "611402 AIR - FAN BOX CASING - SUPPLY"
sketch "HOLE - SUPPLY FAN BOX FEATURE 76" plane through (0, -667, 0) normal (0, 1, 0) x (1, 0, 0) in component "611402 AIR - FAN BOX CASING - SUPPLY"
  circle A0 centre (914.1, -1891.5) radius 2.05
  dimension "d11062" = 4.1
  dimension "d11063" = 914.1
  dimension "d11064" = 1891.5
  measures "d11062" diameter of A0
  measures "d11063" horizontal distance of origin A0.centre
  measures "d11064" vertical distance of origin A0.centre
extrude "CUT - SUPPLY FAN BOX FEATURE 76" cut sketch "HOLE - SUPPLY FAN BOX FEATURE 76" along normal blind 3 bodies 37 in component "611402 AIR - FAN BOX CASING - SUPPLY"
component "610101 AIR - AIR COLUMN" placed x (1, 0, 0) y (0, 1, 0) z (0, 0, 1) at (0, 0, 0)
component "610201 AIR - SOFFIT" placed x (1, 0, 0) y (0, 1, 0) z (0, 0, 1) at (0, 0, 0)
component "610401 AIR - SUPPLY FAN BOX" placed x (1, 0, 0) y (0, 1, 0) z (0, 0, 1) at (0, 0, 0)
component "611601 AIR - ROOF SLEEVE" placed x (1, 0, 0) y (0, 1, 0) z (0, 0, 1) at (0, 0, 0)
component "611602 AIR - ROOF GRILLE" placed x (1, 0, 0) y (0, 1, 0) z (0, 0, 1) at (0, 0, 0)
component "611106 AIR - COLUMN FOOT PLATE" placed x (1, 0, 0) y (0, 1, 0) z (0, 0, 1) at (0, 0, 0) in component "610101 AIR - AIR COLUMN"
component "611101 AIR - COLUMN FACE - FRONT" placed x (1, 0, 0) y (0, 1, 0) z (0, 0, 1) at (0, 0, 0) in component "610101 AIR - AIR COLUMN"
component "611102 AIR - COLUMN FACE - LEFT" placed x (1, 0, 0) y (0, 1, 0) z (0, 0, 1) at (0, 0, 0) in component "610101 AIR - AIR COLUMN"
component "611107 AIR - COLUMN PLENUM SIDE PLATE - LOW" placed x (1, 0, 0) y (0, 1, 0) z (0, 0, 1) at (0, 0, 0) in component "610101 AIR - AIR COLUMN"
component "611108 AIR - COLUMN PLENUM SIDE PLATE - HIGH" placed x (1, 0, 0) y (0, 1, 0) z (0, 0, 1) at (0, 0, 0) in component "610101 AIR - AIR COLUMN"
component "611104 AIR - COLUMN FILL - FRONT" placed x (1, 0, 0) y (0, 1, 0) z (0, 0, 1) at (0, 0, 0) in component "610101 AIR - AIR COLUMN"
component "611110 AIR - COLUMN FILL - LEFT" placed x (1, 0, 0) y (0, 1, 0) z (0, 0, 1) at (0, 0, 0) in component "610101 AIR - AIR COLUMN"
component "611105 AIR - KICK GRILLE - FRONT" placed x (1, 0, 0) y (0, 1, 0) z (0, 0, 1) at (0, 0, 0) in component "610101 AIR - AIR COLUMN"
component "611111 AIR - KICK GRILLE - LEFT" placed x (1, 0, 0) y (0, 1, 0) z (0, 0, 1) at (0, 0, 0) in component "610101 AIR - AIR COLUMN"
component "618101 AIR - SENSOR HUB ZONE - HOLD" placed x (1, 0, 0) y (0, 1, 0) z (0, 0, 1) at (0, 0, 0) in component "610101 AIR - AIR COLUMN"
component "611103 AIR - COLUMN CORNER ANGLE - FRONT" placed x (1, 0, 0) y (0, 1, 0) z (0, 0, 1) at (961, -317, 2) in component "610101 AIR - AIR COLUMN"
component "611103 AIR - COLUMN CORNER ANGLE - FRONT" placed x (-1, 0, 0) y (0, 1, 0) z (0, 0, -1) at (1161, -317, 2120) in component "610101 AIR - AIR COLUMN"
component "611109 AIR - COLUMN CORNER ANGLE - BACK" placed x (1, 0, 0) y (0, 1, 0) z (0, 0, 1) at (0, 0, 0) in component "610101 AIR - AIR COLUMN"
component "610301 AIR - SPLITTER CARTRIDGE - COMMON (SUPPLY)" placed x (1, 0, 0) y (0, 1, 0) z (0, 0, 1) at (0, 0, 0) in component "610101 AIR - AIR COLUMN"
component "611301 AIR - CARTRIDGE CASING" placed x (1, 0, 0) y (0, 1, 0) z (0, 0, 1) at (0, 0, 0) in component "610301 AIR - SPLITTER CARTRIDGE - COMMON (SUPPLY)"
component "611302 AIR - CARTRIDGE FILL - LAYER 50" placed x (1, 0, 0) y (0, 1, 0) z (0, 0, 1) at (990, -634.14, 140) in component "610301 AIR - SPLITTER CARTRIDGE - COMMON (SUPPLY)"
component "611302 AIR - CARTRIDGE FILL - LAYER 50" placed x (1, 0, 0) y (0, 1, 0) z (0, 0, 1) at (990, -504.14, 140) in component "610301 AIR - SPLITTER CARTRIDGE - COMMON (SUPPLY)"
component "611302 AIR - CARTRIDGE FILL - LAYER 50" placed x (1, 0, 0) y (0, 1, 0) z (0, 0, 1) at (990, -374.14, 140) in component "610301 AIR - SPLITTER CARTRIDGE - COMMON (SUPPLY)"
component "611201 AIR - SOFFIT UNDERSIDE - LEFT HINGED" placed x (1, 0, 0) y (0, 1, 0) z (0, 0, 1) at (0, 0, 0) in component "610201 AIR - SOFFIT"
component "611207 AIR - SOFFIT UNDERSIDE - RIGHT HINGED" placed x (1, 0, 0) y (0, 1, 0) z (0, 0, 1) at (0, 0, 0) in component "610201 AIR - SOFFIT"
component "611208 AIR - SOFFIT UNDERSIDE - FIXED OVER THE COLUMN" placed x (1, 0, 0) y (0, 1, 0) z (0, 0, 1) at (0, 0, 0) in component "610201 AIR - SOFFIT"
component "611202 AIR - SOFFIT FACE - FRONT" placed x (1, 0, 0) y (0, 1, 0) z (0, 0, 1) at (0, 0, 0) in component "610201 AIR - SOFFIT"